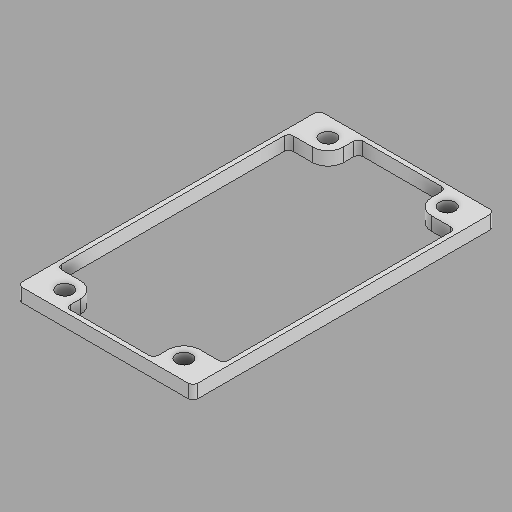
# Autodesk Inventor part: Buck_Converter_10A_spacer
Saved by Autodesk Inventor 2025 (Build 290162000, 162)
## iProperties
Created: 2024-11-13
Part Number: Buck_Converter_10A_spacer
Material: 일반
Document SubType Name: Modeling
Designer: OSB
Density: 0.84152 g/cm^3
Appearance: 기본값
Mass: 1 g
Surface Area: 21.3869 cm^2
Volume: 1.18833 cm^3
Author: OSB
Autodesk Inventor part; units mm, degrees
ref_plane "YZ Plane" through (0, 0, 0) normal (1, 0, 0) x (0, 1, 0)
ref_plane "XZ Plane" through (0, 0, 0) normal (0, 1, 0) x (-1, 0, 0)
ref_plane "XY Plane" through (0, 0, 0) normal (0, 0, 1) x (1, 0, 0)
sketch "스케치1" plane through (0, 0, 0) normal (0, 0, 1) x (1, 0, 0)
  line L0 (-29.25, 13.25) -> (29.25, 13.25) construction
  line L1 (29.25, 13.25) -> (29.25, -13.25) construction
  line L2 (29.25, -13.25) -> (-29.25, -13.25) construction
  line L3 (-29.25, -13.25) -> (-29.25, 13.25) construction
  line L4 (-29.25, 13.25) -> (29.25, -13.25) construction
  line L5 (29.25, 13.25) -> (-29.25, -13.25) construction
  line L6 (-32.5, -18.5) -> (32.5, -18.5)
  line L7 (32.5, -18.5) -> (32.5, 18.5)
  line L8 (32.5, 18.5) -> (-32.5, 18.5)
  line L9 (-32.5, 18.5) -> (-32.5, -18.5)
  line L10 (-32.5, -18.5) -> (32.5, 18.5) construction
  line L11 (32.5, -18.5) -> (-32.5, 18.5) construction
  circle A0 centre (-29.25, 13.25) radius 1.75
  circle A1 centre (29.25, 13.25) radius 1.75
  circle A2 centre (-29.25, -13.25) radius 1.75
  circle A3 centre (29.25, -13.25) radius 1.75
  circle A4 centre (-29.25, 13.25) radius 3.5
  circle A5 centre (29.25, 13.25) radius 3.5
  circle A6 centre (-29.25, -13.25) radius 3.5
  circle A7 centre (29.25, -13.25) radius 3.5
  line L12 (33.5, 19.5) -> (33.5, -19.5)
  line L13 (33.5, -19.5) -> (-33.5, -19.5)
  line L14 (-33.5, -19.5) -> (-33.5, 19.5)
  line L15 (-33.5, 19.5) -> (33.5, 19.5)
  line L16 (29.25, 16.75) -> (32.5, 16.75)
  line L17 (29.25, 9.75) -> (32.5, 9.75)
  line L18 (29.25, -9.75) -> (32.5, -9.75)
  line L19 (-29.25, -9.75) -> (-32.5, -9.75)
  line L20 (-29.25, 9.75) -> (-32.5, 9.75)
  line L21 (-29.25, 16.75) -> (-32.5, 16.75)
  line L22 (25.75, -13.25) -> (25.75, -18.5)
  line L23 (-25.75, -13.25) -> (-25.75, -18.5)
  line L24 (-25.75, 13.25) -> (-25.75, 18.5)
  line L25 (25.75, 13.25) -> (25.75, 18.5)
  point P0 (0, 0)
  point P1 (29.25, -16.75)
  point P2 (32.5, -14.549)
  point P3 (-32.5, -14.549)
  point P4 (-32.5, 11.951)
  point P5 (-32.5, 14.549)
  point P6 (32.5, -11.951)
  point P7 (-32.5, -11.951)
  point P8 (32.5, 14.549)
  point P9 (32.5, 11.951)
  dimension "d0" = 58.5
  dimension "d1" = 26.5
  dimension "d2" = 65
  dimension "d3" = 37
  dimension "d4" = 3.5
  dimension "d5" = 3.5
  dimension "d7" = 3.5
  dimension "d8" = 3.5
  dimension "d9" = 7
  dimension "d10" = 7
  dimension "d11" = 7
  dimension "d12" = 7
  dimension "d13" = 1
  constraints: 52 end point, 21 point on line, 11 point on circle, 10 perpendicular, 8 centre point, 8 coincident, 7 tangent, 6 parallel, 4 midpoint, 2 horizontal, 3 other
  measures "d0" distance of L1.end L2.end
  measures "d1" distance of L0.end L1.end
  measures "d2" distance of L8.end L7.end
  measures "d3" distance of L7.end L6.end
  measures "d4" diameter of A0
  measures "d5" diameter of A1
  measures "d7" diameter of A2
  measures "d8" diameter of A3
  measures "d9" diameter of A4
  measures "d10" diameter of A5
  measures "d11" diameter of A6
  measures "d12" diameter of A7
  measures "d13" distance between parallel lines of L7 L12
extrude "돌출1" add sketch "스케치1" along normal blind 3 contours L9 A6 L23 L6 | A6 L9 | L9 A6 | L22 A7 L7 L6 | L9 L19 A6 | A7 L7 | L7 A7 | L18 L7 A7 | L9 A4 L20 | A4 L9 | L9 A4 | L17 A5 L7 | L9 L21 A4 | A4 L21 L9 L8 L24 | A5 L7 | L7 A5 | A5 L16 L7 | L25 L8 L7 L16 A5 | L12 L13 L14 L15
fillet "모깎기1" radius 1 12 edges at (33.5, 19.5, 1.5) (-33.5, 19.5, 1.5) (33.5, -19.5, 1.5) (-33.5, -19.5, 1.5) (-32.5, -9.75, 1.5) (-32.5, 9.75, 1.5) (32.5, -9.75, 1.5) (32.5, 9.75, 1.5) (25.75, -18.5, 1.5) (25.75, 18.5, 1.5) (-25.75, 18.5, 1.5) (-25.75, -18.5, 1.5)
equation "\"d4\" = d8"
equation "\"d5\" = d8"
equation "\"d7\" = d8"
equation "\"d9\" = d12"
equation "\"d10\" = d12"
equation "\"d11\" = d12"
